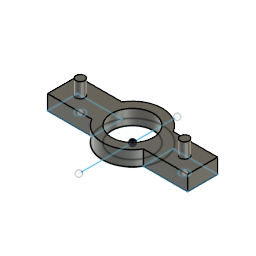
motorhalter (Autodesk Fusion 360 design; units mm, degrees)
Autodesk Fusion 360 part; units mm, degrees
sketch "Skizze1" plane through (0, 0, 0) normal (0, 0, 1) x (1, 0, 0)
  circle A0 centre (0, 0) radius 14
  circle A1 centre (0, 0) radius 20
  circle A2 centre (-35, 0) radius 3
  circle A3 centre (35, 0) radius 3
  line L0 (-17.236, 10.1449) -> (-47, 10.1449)
  line L1 (-47, 10.1449) -> (-47, -10)
  line L2 (-47, -10) -> (-17.236, -10)
  line L3 (-17.236, -10) -> (-17.236, 10.1449)
  line L4 (0, 30) -> (0, -36)
  line L5 (17.236, 10.1449) -> (47, 10.1449)
  line L6 (47, 10.1449) -> (47, -10)
  line L7 (47, -10) -> (17.236, -10)
  line L8 (17.236, -10) -> (17.236, 10.1449)
  dimension "d1" = 28
  dimension "d2" = 40
  dimension "d3" = 6
  dimension "d4" = 35
  dimension "d5" = 6
  dimension "d6" = 35
  constraint coincident A0.centre A1.centre
  constraint concentric A0 A1
  constraint horizontal L0
  constraint vertical L1
  constraint horizontal L2
  constraint vertical L3
  constraint coincident A1 L0.start
  constraint vertical L4
  constraint symmetric L0.start L4 L5.start
  constraint symmetric L0.end L4 L5.end
  constraint symmetric L1.end L4 L6.end
  constraint symmetric L2.end L4 L7.end
  measures "d1" diameter of A0
  measures "d2" diameter of A1
  measures "d3" diameter of A2
  measures "d4" distance of A0.centre A2.centre
  measures "d5" diameter of A3
  measures "d6" distance of A0.centre A3.centre
extrude "Extrusion1" add sketch "Skizze1" along normal blind 10 contours A0 A1 L4 L7 L8 | A0 A1 L2 L3 L4 | A1 L5 L6 L7 | A1 L7 L8 | A1 L2 L3 | A1 L0 L1 L2
extrude "Extrusion2" add sketch "Skizze1" along normal blind 20 contours A2 | A3
